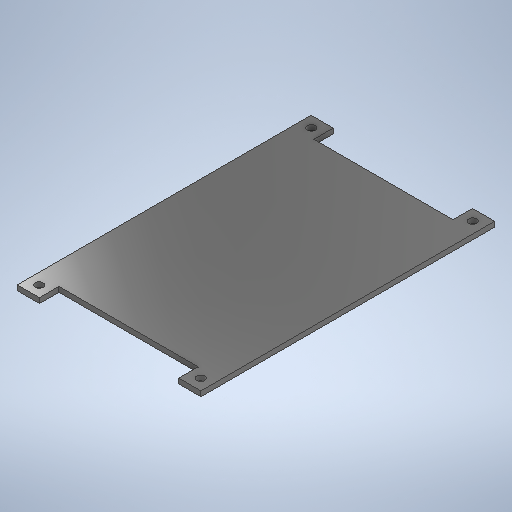
# Autodesk Inventor part: CHIWU
Saved by Autodesk Inventor 2025.3 (Build 293356000, 356)
## iProperties
Created: 2026-09-08
Part Number: CHIWU
Material: 氮化硅
Document SubType Name: Modeling
Designer: shfzf
Density: 3.18 g/cm^3
Appearance: 铬 - 黑色抛光
Author: shfzf
Autodesk Inventor part; units mm, degrees
ref_plane "YZ Plane" through (0, 0, 0) normal (1, 0, 0) x (0, 1, 0)
ref_plane "XZ Plane" through (0, 0, 0) normal (0, 1, 0) x (-1, 0, 0)
ref_plane "XY Plane" through (0, 0, 0) normal (0, 0, 1) x (1, 0, 0)
sketch "草图1" plane through (0, 0, 0) normal (0, 1, 0) x (-1, 0, 0)
  line L0 (22, 40.25) -> (-22, 40.25)
  line L1 (-29, 40.25) -> (-29, -40.25)
  line L2 (-22, -40.25) -> (22, -40.25)
  line L3 (29, -40.25) -> (29, 40.25)
  line L4 (-29, 46.4) -> (-29, -46.4)
  line L5 (29, -46.4) -> (29, 46.4)
  line L6 (22, 46.4) -> (22, 40.25)
  line L7 (22, -40.25) -> (22, -46.4)
  circle A0 centre (25.5, 43) radius 1.25
  line L8 (0, 0) -> (0, -9.8133)
  line L9 (0, 0) -> (10.2519, 0)
  circle A1 centre (25.5, -43) radius 1.25
  line L10 (25.5, 43) -> (25.5, -43) construction
  line L11 (-22, 46.4) -> (-22, 40.25)
  line L12 (-22, -40.25) -> (-22, -46.4)
  circle A2 centre (-25.5, 43) radius 1.25
  circle A3 centre (-25.5, -43) radius 1.25
  line L13 (29, 46.4) -> (22, 46.4)
  line L14 (-22, 46.4) -> (-29, 46.4)
  line L15 (-29, -46.4) -> (-22, -46.4)
  line L16 (22, -46.4) -> (29, -46.4)
  point P0 (0, 40.25)
  point P1 (29, 0)
  point P2 (-29, 0)
  dimension "d0" = 58
  dimension "d1" = 80.5
  dimension "d2" = 92.8
  dimension "d3" = 7
  dimension "d4" = 2.5
  dimension "d5" = 3.5
  dimension "d6" = 86
  constraints: 34 end point, 7 parallel, 7 symmetric about line, 5 midpoint, 4 centre point, 4 horizontal, 4 perpendicular, 4 point on line, 2 horizontal alignment, 2 vertical, 1 vertical alignment, 3 other
  measures "d0" distance of L3.end L1.start
  measures "d1" distance of L3.start L3.end
  measures "d2" distance of L5.start L5.end
  measures "d3" distance between parallel lines of L6 L5
  measures "d4" diameter of A0
  measures "d5" distance from line of L5 L10.start
  measures "d6" distance of L10.start L10.end
extrude "拉伸1" add sketch "草图1" along normal blind 1.6
